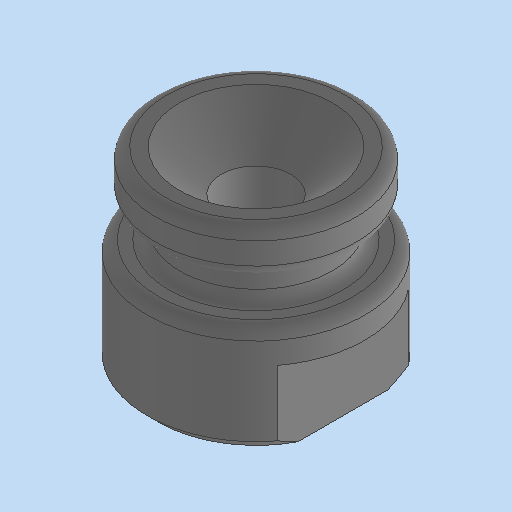
# Autodesk Inventor part: MM0948AN100_G01_189
Saved by Autodesk Inventor 2023.3 (Build 273359000, 359)
## iProperties
Created: 2023-12-11
Part Number: MM0948AN100_G01_189
Material: 1.4305 X8CrNiS18-9
Description: =<RBPARTNOTITLE2>
Document SubType Name: Modeling
Designer: SFO3AN
Mass: 3.65428 g
Surface Area: 4.92253 cm^2
Volume: 0.462567 cm^3
Density: 7.9 g/cm^3
Appearance: Stahl - rostfrei AnP
RBPARTMADEOF: 8,6 x 10 x 10 (FM)
RBDRAWINGMISSINGSPEC: --
AnP_Kategorie: 1
RBPARTNOTITLE2: Anfertigungsteil
RBSURFACE: --
RBPARTNOTITLE1: manufactured part
RBSURFACE2: --
AnP_Material: =<Material>
RBMATERIAL: =<Material>
RBMATNO: =<Part Number>
RBPARTNO: SIEHE MNR
MaxAbmaße: 8,6 x 10 x 10 (FM)
Author: SFO3AN
Keywords: =<RBPARTMADEOF>
Comments: =<RBSURFACE2>
Revision Number: 01
Autodesk Inventor part; units mm, degrees
ref_plane "YZ Plane" through (0, 0, 0) normal (1, 0, 0) x (0, 1, 0)
ref_plane "XZ Plane" through (0, 0, 0) normal (0, 1, 0) x (-1, 0, 0)
ref_plane "XY Plane" through (0, 0, 0) normal (0, 0, 1) x (1, 0, 0)
sketch "Skizze2" plane through (0, 0, 0) normal (0, 1, 0) x (-1, 0, 0)
  line L0 (0, 0) -> (5, 0)
  line L1 (5, 0) -> (5, 5)
  line L2 (5, 5) -> (3.5, 5)
  line L3 (3.5, 5) -> (3.5, 6.7)
  line L4 (3.5, 6.7) -> (4.6, 6.7)
  line L5 (4.6, 6.7) -> (4.6, 8.7)
  line L6 (4.6, 8.7) -> (0, 8.7)
  line L7 (0, 8.7) -> (0, 0)
  line L8 (0, -1.74) -> (0, 10.44) projected
  dimension "d0" = 5
  dimension "d1" = 1.7
  dimension "d3" = 5
  dimension "d4" = 2
  dimension "d59" = 1.5
  dimension "d60" = 4.6
  constraints: 16 end point, 6 perpendicular, 1 horizontal
  measures "d0" distance between parallel lines of L7 L1
  measures "d1" distance between parallel lines of L4 L2
  measures "d3" distance between parallel lines of L0 L2
  measures "d4" distance between parallel lines of L4 L6
  measures "d59" distance between parallel lines of L1 L3
  measures "d60" distance of L5.end L6.end
revolve "Umdrehung1" add sketch "Skizze2" angle 360 about axis through (0, 0, -10) along (0, 0, 1)
sketch "Skizze3" plane through (0, 0, 0) normal (0, 0, -1) x (-1, 0, 0)
  circle A0 centre (0, 0) radius 3
  dimension "d6" = 6
  constraints: 1 centre point, 1 coincident
  measures "d6" diameter of A0
extrude "Extrusion1" [suppressed]
sketch "Skizze4" plane through (0, 0, -2) normal (0, 0, -1) x (-1, 0, 0)
  point P0 (0, 0)
  point P1 (0, 0)
  constraints: 1 coincident
hole "Bohrung1" [suppressed]
sketch "Skizze5" plane through (0, 0, 0) normal (0, 0, -1) x (-1, 0, 0)
  circle A0 centre (0, 0) radius 2
  dimension "d16" = 4
  constraints: 1 centre point, 1 coincident
  measures "d16" diameter of A0
extrude "Extrusion2" [suppressed]
thread "Gewinde1" size "M4x0.7" designation "M4" class "6g" standard "ISO Metric profile" full length
chamfer "Fase1" [suppressed]
sketch "Skizze6" plane through (0, 0, 0) normal (0, 1, 0) x (-1, 0, 0)
  line L0 (0, -1) -> (0, 6) projected
  line L1 (7, 0) -> (-7, 0) projected
  line L2 (-5, 0) -> (-5, 5) projected
  line L3 (5, 0) -> (5, 5) projected
  line L4 (5, 0) -> (4, 0)
  line L5 (4, 0) -> (4, 3.5)
  line L6 (4, 3.5) -> (5, 3.5)
  line L7 (5, 3.5) -> (5, 0)
  line L8 (-5, 0) -> (-4, 0)
  line L9 (-4, 0) -> (-4, 3.5)
  line L10 (-4, 3.5) -> (-5, 3.5)
  line L11 (-5, 3.5) -> (-5, 0)
  line L12 (5, 5) -> (-5, 5) projected
  point P0 (0, 0)
  point P1 (5, 3.5)
  point P2 (4, 0)
  point P3 (-4, 0)
  dimension "d24" = 8
  dimension "d65" = 3.5
  constraints: 16 end point, 4 parallel, 2 horizontal, 2 perpendicular, 1 collinear, 1 other
  measures "d24" distance between parallel lines of L5 L9
  measures "d65" distance of L8.end L9.end
extrude "Extrusion3" cut sketch "Skizze6" along normal through all both and the other way through all contours L5 L6 L3 L1 | L1 L2 L10 L9
chamfer "Fase3" [suppressed]
sketch "Skizze7" plane through (0, 0, 0) normal (1, 0, 0) x (0, 1, 0)
  line L0 (-0.4, 0) -> (2.4, 0) projected
  line L1 (2, 0) -> (1.85, 0)
  line L2 (1.45, -0.8) -> (1.45, -0.4)
  line L3 (1.45, -0.8) -> (2, -1.75)
  arc A0 (1.85, 0) -> (1.45, -0.4) centre (1.85, -0.4) ccw
  line L4 (2, 0) -> (2, -1.75)
  line L5 (0, -2.1166) -> (0, 0.4494) projected
  point P0 (0, 0)
  point P1 (1.45, 0)
  point P2 (1.925, 0)
  dimension "d35" = 0.4
  dimension "d37" = 0.8
  dimension "d38" = 1.75
  dimension "d49" = 0.55
  dimension "d50" = 2
  constraints: 9 end point, 3 point on line, 2 point on circle, 2 tangent, 1 centre point, 1 midpoint, 1 perpendicular, 1 vertical
  measures "d35" radius of A0
  measures "d37" vertical distance of point (1.925, 0) L2.start
  measures "d38" distance from line of L3.end L0
  measures "d49" distance between parallel lines of L4 L2
  measures "d50" distance between parallel lines of L5 L4
revolve "Umdrehung2" [suppressed]
fillet "Rundung3" [suppressed]
sketch "Skizze9" plane through (0, 0, 8.7) normal (0, 0, 1) x (1, 0, 0)
  line L0 (-7, 0) -> (7, 0) projected
  line L1 (0, -7) -> (0, 7) projected
  point P0 (0, 0)
  point P1 (0, 0)
  constraints: 1 coincident
hole "Bohrung3" at (0, 0, 8.7) direction (0, 0, -1) diameter 3.2 end through all countersink diameter 7 countersink angle 90 clearance for "Innensechskant-Senkkopfschraube ISO 10642" size "M3" standard "ISO"
fillet "Rundung4" radius 0.5 2 edges at (3.5, 0, 5) (3.5, 0, 6.7)
fillet "Rundung5" radius 0.5 3 edges at (4.6, 0, 8.7) (4.6, 0, 6.7) (5, 0, 5)
chamfer "Fase4" distance 0.5 angle 45 2 edges at (0, 5, 0) (0, -5, 0)
